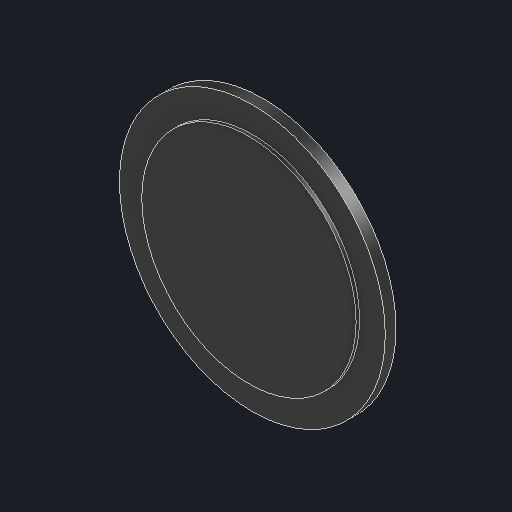
# Autodesk Inventor part: logo_cap
Saved by Autodesk Inventor 2027.1 (Build 311270010, 270A)
## iProperties
Created: 2026-11-04
Part Number: logo_cap
Material: Generic
Description: Latitude pivot cap (Celestron logo side)
Document SubType Name: Modeling
Designer: Claude (from photos)
Density: 1 g/cm^3
Appearance: Glossy - Black
Author: alexg
Autodesk Inventor part; units mm, degrees
ref_plane "YZ Plane" through (0, 0, 0) normal (1, 0, 0) x (0, 1, 0)
ref_plane "Work Plane1" through (0, 0, 41) normal (0, 0, 1) x (1, 0, 0)
sketch "Logo cap sketch" plane through (0, 0, 41) normal (0, 0, 1) x (1, 0, 0)
  circle A0 centre (0, 64) radius 31
  constraints: 1 centre point
extrude "Logo cap" add sketch "Logo cap sketch" along normal blind 2.5
ref_plane "Work Plane2" through (0, 0, 43.5) normal (0, 0, 1) x (1, 0, 0)
sketch "Emblem sketch" plane through (0, 0, 43.5) normal (0, 0, 1) x (1, 0, 0)
  circle A0 centre (0, 64) radius 25
  constraints: 1 centre point
extrude "Emblem" add sketch "Emblem sketch" along normal blind 0.8
body "Solid1"
